Bean Bag (Autodesk Fusion 360 design; units mm, degrees)
part number: 2026-10-17-17-00-50-315
Autodesk Fusion 360 part; units mm, degrees
sketch "Sketch1" plane through (0, 0, 0) normal (0, 0, 1) x (1, 0, 0)
  line L0 (65, 65) -> (-65, 65)
  line L1 (-65, 65) -> (-65, -65)
  line L2 (-65, -65) -> (65, -65)
  line L3 (65, -65) -> (65, 65)
  line L4 (65, 65) -> (-65, -65) construction
  line L5 (-65, 65) -> (65, -65) construction
  dimension "d1" = 130
  dimension "d2" = 130
  constraint horizontal L0
  constraint perpendicular L0 L1
  constraint parallel L0 L2
  constraint parallel L1 L3
  constraint coincident L4 origin
  constraint coincident L5 origin
  measures "d1" distance of L1.end L2.end
  measures "d2" distance of L0.end L1.end
extrude "Extrude1" add sketch "Sketch1" along normal blind 50
fillet "Fillet1" radius 25 12 edges at (0, -65, 50) (-65, 0, 50) (-65, -65, 25) (65, -65, 25) (65, 0, 50) (65, 0, 0) (0, -65, 0) (65, 65, 25) (0, 65, 50) (-65, 0, 0) (0, 65, 0) (-65, 65, 25)
